01_yoke_short_stiff_V6_editable (Autodesk Fusion 360 design; units mm, degrees)
part number: 2026-10-22-00-02-15-116
Autodesk Fusion 360 part; units mm, degrees
ref_plane "作業平面1" through (0, -36.5, 0) normal (0, 1, 0) x (0, 0, 1)
sketch "スケッチ1" plane through (0, -36.5, 0) normal (0, 1, 0) x (1, 0, 0)
  circle A0 centre (-2, -34) radius 13
  dimension "sc_brush_axis_y" = 2.7629
  dimension "sc_screw_clearance" = 3.4
  dimension "sc_head_dia" = 6.2
  dimension "sc_head_depth" = 3.2
  dimension "d7" = 26
  measures "d7" diameter of A0
extrude "V6_negative_horn_pad (1)" add sketch "スケッチ1" along normal blind 19.45
ref_plane "作業平面2" through (0, 0, 21) normal (0, 0, 1) x (1, 0, 0)
sketch "スケッチ2" plane through (0, 0, 21) normal (0, 0, 1) x (1, 0, 0)
  line L0 (-2, -36.5) -> (54, -36.5)
  line L1 (54, -36.5) -> (54, -28.5)
  line L2 (54, -28.5) -> (-2, -28.5)
  line L3 (-2, -28.5) -> (-2, -36.5)
extrude "V6_deep_negative_rail (1)" add sketch "スケッチ2" along normal blind 26
ref_plane "作業平面3" through (0, 0, 35.5) normal (0, 0, 1) x (1, 0, 0)
sketch "スケッチ3" plane through (0, 0, 35.5) normal (0, 0, 1) x (1, 0, 0)
  line L0 (47, -36.5) -> (54, -36.5)
  line L1 (54, -36.5) -> (54, 35.5)
  line L2 (54, 35.5) -> (47, 35.5)
  line L3 (47, 35.5) -> (47, -36.5)
extrude "V6_low_box_crossmember (1)" add sketch "スケッチ3" along normal blind 11.5
ref_plane "作業平面4" through (0, 0, 21) normal (0, 0, 1) x (1, 0, 0)
sketch "スケッチ4" plane through (0, 0, 21) normal (0, 0, 1) x (1, 0, 0)
  line L0 (-2, 27.5) -> (54, 27.5)
  line L1 (54, 27.5) -> (54, 35.5)
  line L2 (54, 35.5) -> (-2, 35.5)
  line L3 (-2, 35.5) -> (-2, 27.5)
extrude "V6_deep_positive_rail (1)" add sketch "スケッチ4" along normal blind 26
ref_plane "作業平面5" through (0, 20.2, 0) normal (0, 1, 0) x (0, 0, 1)
sketch "スケッチ5" plane through (0, 20.2, 0) normal (0, 1, 0) x (1, 0, 0)
  circle A0 centre (-2, -34) radius 13
  dimension "d24" = 26
  measures "d24" diameter of A0
extrude "V6_positive_horn_pad (1)" add sketch "スケッチ5" along normal blind 15.3
ref_plane "作業平面6" through (0, 0, 21) normal (0, 0, 1) x (1, 0, 0)
sketch "スケッチ6" plane through (0, 0, 21) normal (0, 0, 1) x (1, 0, 0)
  line L0 (47, 27.5) -> (69.2, 27.5)
  line L1 (69.2, 27.5) -> (69.2, 35.5)
  line L2 (69.2, 35.5) -> (47, 35.5)
  line L3 (47, 35.5) -> (47, 27.5)
extrude "V6_full_width_under_socket_gusset (1)" add sketch "スケッチ6" along normal blind 18.5
ref_plane "作業平面7" through (0, 0, 29.5) normal (0, 0, 1) x (1, 0, 0)
sketch "スケッチ7" plane through (0, 0, 29.5) normal (0, 0, 1) x (1, 0, 0)
  line L0 (54.8, 23.4629) -> (69.2, 23.4629)
  line L1 (69.2, 23.4629) -> (69.2, 41.5629)
  line L2 (69.2, 41.5629) -> (54.8, 41.5629)
  line L3 (54.8, 41.5629) -> (54.8, 23.4629)
extrude "V6_fixed_cell_floor (1)" add sketch "スケッチ7" along normal blind 10
ref_plane "作業平面8" through (0, 0, 39.5) normal (0, 0, 1) x (1, 0, 0)
sketch "スケッチ8" plane through (0, 0, 39.5) normal (0, 0, 1) x (1, 0, 0)
  line L0 (54.8, 23.4629) -> (57.3, 23.4629)
  line L1 (57.3, 23.4629) -> (57.3, 41.5629)
  line L2 (57.3, 41.5629) -> (54.8, 41.5629)
  line L3 (54.8, 41.5629) -> (54.8, 23.4629)
extrude "V6_fixed_socket_wall_54.8 (1)" add sketch "スケッチ8" along normal blind 10
ref_plane "作業平面9" through (0, 0, 39.5) normal (0, 0, 1) x (1, 0, 0)
sketch "スケッチ9" plane through (0, 0, 39.5) normal (0, 0, 1) x (1, 0, 0)
  line L0 (66.7, 23.4629) -> (69.2, 23.4629)
  line L1 (69.2, 23.4629) -> (69.2, 41.5629)
  line L2 (69.2, 41.5629) -> (66.7, 41.5629)
  line L3 (66.7, 41.5629) -> (66.7, 23.4629)
extrude "V6_fixed_socket_wall_66.7 (1)" add sketch "スケッチ9" along normal blind 10
ref_plane "作業平面10" through (0, 0, 45.9) normal (0, 0, 1) x (1, 0, 0)
sketch "スケッチ10" plane through (0, 0, 45.9) normal (0, 0, 1) x (1, 0, 0)
  line L0 (54.8, 27.4629) -> (69.2, 27.4629)
  line L1 (69.2, 27.4629) -> (69.2, 41.5629)
  line L2 (69.2, 41.5629) -> (54.8, 41.5629)
  line L3 (54.8, 41.5629) -> (54.8, 27.4629)
extrude "V6_fixed_socket_roof (1)" add sketch "スケッチ10" along normal blind 3.6
ref_plane "作業平面11" through (0, 0, 39.5) normal (0, 0, 1) x (1, 0, 0)
sketch "スケッチ11" plane through (0, 0, 39.5) normal (0, 0, 1) x (1, 0, 0)
  line L0 (57.3, 38.8629) -> (66.7, 38.8629)
  line L1 (66.7, 38.8629) -> (66.7, 41.5629)
  line L2 (66.7, 41.5629) -> (57.3, 41.5629)
  line L3 (57.3, 41.5629) -> (57.3, 38.8629)
extrude "V6_fixed_socket_end_stop (1)" add sketch "スケッチ11" along normal blind 6.4
ref_plane "作業平面12" through (0, -36.6, 0) normal (0, 1, 0) x (0, 0, 1)
sketch "スケッチ12" plane through (0, -36.6, 0) normal (0, 1, 0) x (1, 0, 0)
  line L0 (19, -26) -> (36, -26)
  arc A0 (36, -42) -> (36, -26) centre (36, -34) ccw
  line L1 (36, -42) -> (19, -42)
  arc A1 (19, -26) -> (19, -42) centre (19, -34) ccw
extrude "V6_rounded_rail_window_negative (1)" cut sketch "スケッチ12" along normal blind 8.2
ref_plane "作業平面13" through (0, 27.4, 0) normal (0, 1, 0) x (0, 0, 1)
sketch "スケッチ13" plane through (0, 27.4, 0) normal (0, 1, 0) x (1, 0, 0)
  line L0 (19, -26) -> (36, -26)
  arc A0 (36, -42) -> (36, -26) centre (36, -34) ccw
  line L1 (36, -42) -> (19, -42)
  arc A1 (19, -26) -> (19, -42) centre (19, -34) ccw
extrude "V6_rounded_rail_window_positive (1)" cut sketch "スケッチ13" along normal blind 8.2
ref_plane "作業平面14" through (0, -28.5, 0) normal (0, 1, 0) x (0, 0, 1)
sketch "スケッチ14" plane through (0, -28.5, 0) normal (0, 1, 0) x (1, 0, 0)
  line L0 (49, -38) -> (52, -38)
  line L1 (52, -38) -> (52, -44.5)
  line L2 (52, -44.5) -> (49, -44.5)
  line L3 (49, -44.5) -> (49, -38)
extrude "V6_box_beam_hollow_core" cut sketch "スケッチ14" along normal blind 56
ref_plane "作業平面15" through (0, -36.6, 0) normal (0, 1, 0) x (0, 0, 1)
sketch "スケッチ15" plane through (0, -36.6, 0) normal (0, 1, 0) x (1, 0, 0)
  circle A0 centre (-2, -34) radius 3.25
  dimension "d65" = 6.5
  measures "d65" diameter of A0
extrude "V6_negative_central_key (1)" cut sketch "スケッチ15" along normal blind 19.65
ref_plane "作業平面16" through (0, -18.9, 0) normal (0, 1, 0) x (0, 0, 1)
sketch "スケッチ16" plane through (0, -18.9, 0) normal (0, 1, 0) x (1, 0, 0)
  circle A0 centre (-2, -34) radius 4
  dimension "d70" = 8
  measures "d70" diameter of A0
extrude "V6_negative_center_head_relief (1)" cut sketch "スケッチ16" along normal blind 1.9
ref_plane "作業平面17" through (0, -18.2, 0) normal (0, 1, 0) x (0, 0, 1)
sketch "スケッチ17" plane through (0, -18.2, 0) normal (0, 1, 0) x (1, 0, 0)
  circle A0 centre (-2, -34) radius 5.5
  dimension "d75" = 11
  measures "d75" diameter of A0
extrude "V6_fixed_boss_clearance (1)" cut sketch "スケッチ17" along normal blind 1.2
ref_plane "作業平面18" through (0, -36.6, 0) normal (0, 1, 0) x (0, 0, 1)
sketch "スケッチ18" plane through (0, -36.6, 0) normal (0, 1, 0) x (1, 0, 0)
  circle A0 centre (5, -34) radius 1.6
  circle A1 centre (-2, -41) radius 1.6
  circle A2 centre (-9, -34) radius 1.6
  circle A3 centre (-2, -27) radius 1.6
  dimension "d80" = 3.2
  dimension "d81" = 3.2
  dimension "d82" = 3.2
  dimension "d83" = 3.2
  measures "d80" diameter of A0
  measures "d81" diameter of A1
  measures "d82" diameter of A2
  measures "d83" diameter of A3
extrude "V6_negative_M3_shanks" cut sketch "スケッチ18" along normal blind 19.65
ref_plane "作業平面19" through (0, -36.6, 0) normal (0, 1, 0) x (0, 0, 1)
sketch "スケッチ19" plane through (0, -36.6, 0) normal (0, 1, 0) x (1, 0, 0)
  circle A0 centre (5, -34) radius 3.1
  circle A1 centre (-2, -41) radius 3.1
  circle A2 centre (-9, -34) radius 3.1
  circle A3 centre (-2, -27) radius 3.1
  dimension "d88" = 6.2
  dimension "d89" = 6.2
  dimension "d90" = 6.2
  dimension "d91" = 6.2
  measures "d88" diameter of A0
  measures "d89" diameter of A1
  measures "d90" diameter of A2
  measures "d91" diameter of A3
extrude "V6_negative_deep_M3_heads" cut sketch "スケッチ19" along normal blind 9.6
ref_plane "作業平面20" through (0, 20.1, 0) normal (0, 1, 0) x (0, 0, 1)
sketch "スケッチ20" plane through (0, 20.1, 0) normal (0, 1, 0) x (1, 0, 0)
  circle A0 centre (-2, -34) radius 3.25
  dimension "d96" = 6.5
  measures "d96" diameter of A0
extrude "V6_positive_central_key (1)" cut sketch "スケッチ20" along normal blind 15.5
ref_plane "作業平面21" through (0, 20.1, 0) normal (0, 1, 0) x (0, 0, 1)
sketch "スケッチ21" plane through (0, 20.1, 0) normal (0, 1, 0) x (1, 0, 0)
  circle A0 centre (-2, -34) radius 4
  dimension "d101" = 8
  measures "d101" diameter of A0
extrude "V6_positive_center_head_relief (1)" cut sketch "スケッチ21" along normal blind 2.1
ref_plane "作業平面22" through (0, 20.1, 0) normal (0, 1, 0) x (0, 0, 1)
sketch "スケッチ22" plane through (0, 20.1, 0) normal (0, 1, 0) x (1, 0, 0)
  circle A0 centre (5, -34) radius 1.6
  circle A1 centre (-2, -41) radius 1.6
  circle A2 centre (-9, -34) radius 1.6
  circle A3 centre (-2, -27) radius 1.6
  dimension "d106" = 3.2
  dimension "d107" = 3.2
  dimension "d108" = 3.2
  dimension "d109" = 3.2
  measures "d106" diameter of A0
  measures "d107" diameter of A1
  measures "d108" diameter of A2
  measures "d109" diameter of A3
extrude "V6_positive_M3_shanks" cut sketch "スケッチ22" along normal blind 15.5
ref_plane "作業平面23" through (0, 28, 0) normal (0, 1, 0) x (0, 0, 1)
sketch "スケッチ23" plane through (0, 28, 0) normal (0, 1, 0) x (1, 0, 0)
  circle A0 centre (5, -34) radius 3.1
  circle A1 centre (-2, -41) radius 3.1
  circle A2 centre (-9, -34) radius 3.1
  circle A3 centre (-2, -27) radius 3.1
  dimension "d114" = 6.2
  dimension "d115" = 6.2
  dimension "d116" = 6.2
  dimension "d117" = 6.2
  measures "d114" diameter of A0
  measures "d115" diameter of A1
  measures "d116" diameter of A2
  measures "d117" diameter of A3
extrude "V6_positive_deep_M3_heads" cut sketch "スケッチ23" along normal blind 7.6
ref_plane "作業平面24" through (0, 0, 29.5) normal (0, 0, 1) x (1, 0, 0)
sketch "スケッチ24" plane through (0, 0, 29.5) normal (0, 0, 1) x (1, 0, 0)
  circle A0 centre (62, 26.9629) radius 1.7
  circle A1 centre (62, 34.3629) radius 1.7
  dimension "d122" = 3.4
  dimension "d123" = 3.4
  measures "d122" diameter of A0
  measures "d123" diameter of A1
extrude "V6_fixed_M3_clearance (1)" cut sketch "スケッチ24" along normal blind 10
ref_plane "作業平面25" through (0, 0, 29.5) normal (0, 0, 1) x (1, 0, 0)
sketch "スケッチ25" plane through (0, 0, 29.5) normal (0, 0, 1) x (1, 0, 0)
  circle A0 centre (62, 26.9629) radius 3.1
  circle A1 centre (62, 34.3629) radius 3.1
  dimension "d128" = 6.2
  dimension "d129" = 6.2
  measures "d128" diameter of A0
  measures "d129" diameter of A1
extrude "V6_fixed_M3_heads (1)" cut sketch "スケッチ25" along normal blind 3.2
equation "sc_brush_axis_y = 2.7629462 mm" comment "Mid-plane between the existing yoke arms"
equation "sc_screw_clearance = 3.40 mm" comment "Printed base M3 clearance; sensor itself has M3 threaded holes"
equation "sc_head_dia = 6.20 mm" comment "Underside socket-head recess diameter"
equation "sc_head_depth = 3.20 mm" comment "Underside socket-head recess depth; M3x8 gives 5.2 mm engagement"
equation "d122 = sc_screw_clearance"
equation "d123 = sc_screw_clearance"
equation "d128 = sc_head_dia"
equation "d129 = sc_head_dia"
equation "d130 = sc_head_depth"
named bodies: "V6_short_deep_rails_closed_tie_supported_socket"
